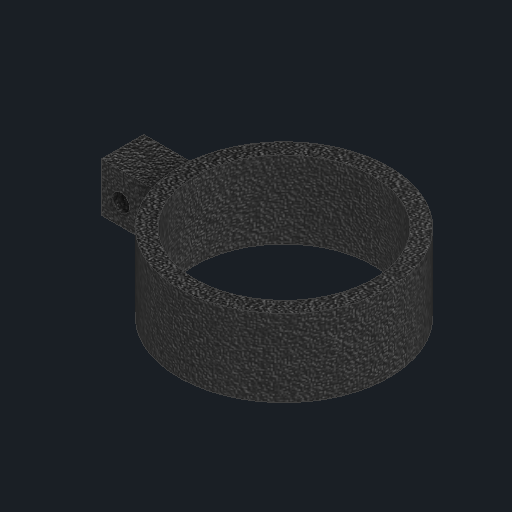
# Autodesk Inventor part: tripod_brace_collar
Saved by Autodesk Inventor 2027.1 (Build 311270010, 270A)
## iProperties
Created: 2026-11-04
Part Number: tripod_brace_collar
Material: Generic
Description: Leg collar with lug for the tray brace arm
Document SubType Name: Modeling
Designer: Claude (from photos)
Density: 1 g/cm^3
Appearance: Black Cast
Author: alexg
Autodesk Inventor part; units mm, degrees
ref_plane "Work Plane1" through (0, -188, 0) normal (0, 1, 0) x (-1, 0, 0)
sketch "Brace collar sketch" plane through (0, -188, 0) normal (0, 1, 0) x (-1, 0, 0)
  circle A0 centre (0, 0) radius 30
  circle A1 centre (0, 0) radius 25.4
  constraints: 2 centre point
extrude "Brace collar" add sketch "Brace collar sketch" against normal blind 22
ref_plane "Work Plane2" through (0, 0, -6) normal (0, 0, 1) x (1, 0, 0)
sketch "Brace lug sketch" plane through (0, 0, -6) normal (0, 0, 1) x (1, 0, 0)
  line L0 (-46, -205) -> (-29, -205)
  line L1 (-29, -205) -> (-29, -191)
  line L2 (-29, -191) -> (-46, -191)
  line L3 (-46, -191) -> (-46, -205)
  constraints: 8 end point, 2 parallel, 1 horizontal, 1 perpendicular
extrude "Brace lug" add sketch "Brace lug sketch" along normal blind 12
ref_plane "Work Plane3" through (0, 0, -10) normal (0, 0, 1) x (1, 0, 0)
sketch "Pin hole sketch" plane through (0, 0, -10) normal (0, 0, 1) x (1, 0, 0)
  circle A0 centre (-40.5553, -199.1388) radius 2.5
  constraints: 1 centre point
extrude "Pin hole" cut sketch "Pin hole sketch" along normal blind 20
body "Solid1"
